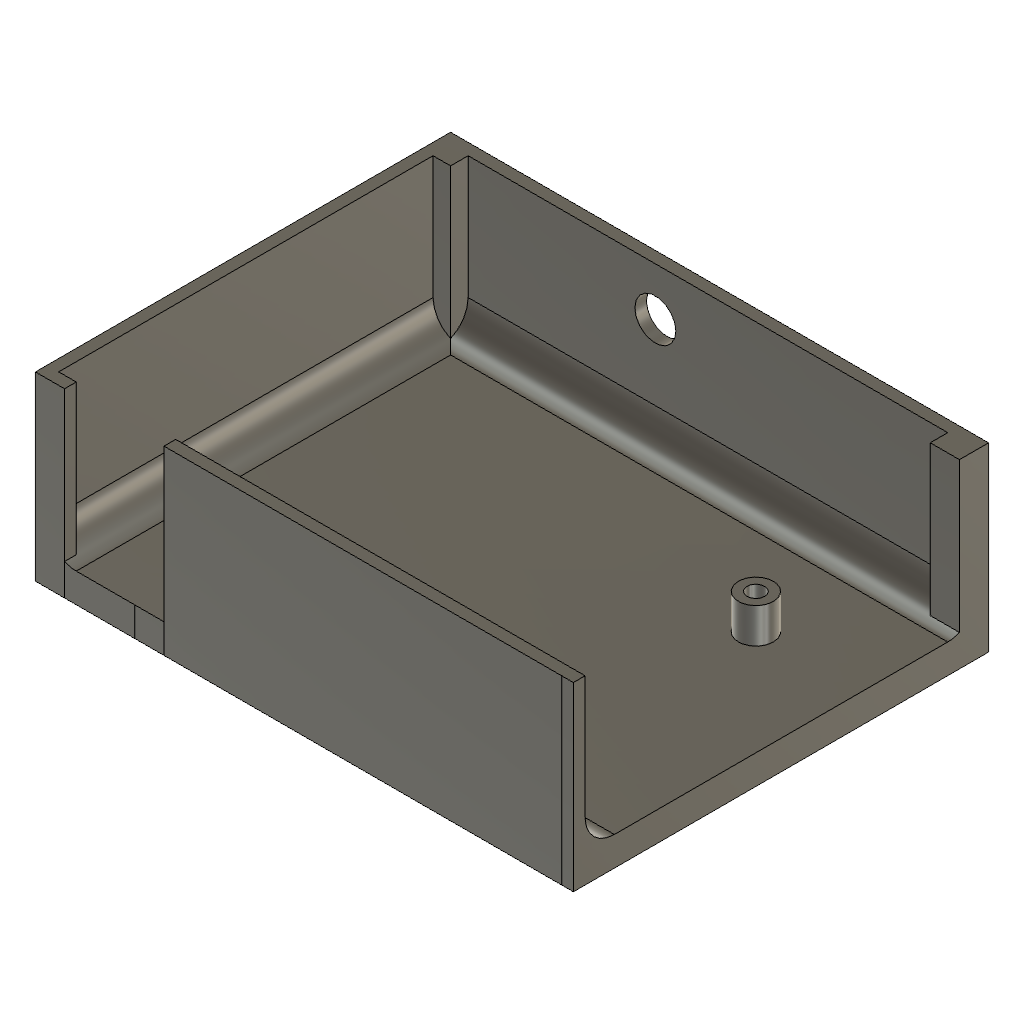
HAB2 Recovery Circuit Case (Autodesk Fusion 360 design; units mm, degrees)
part number: 2026-10-17-16-52-14-798
Autodesk Fusion 360 part; units mm, degrees
sketch "Sketch1" plane through (0, 0, 0) normal (0, 0, 1) x (1, 0, 0)
  line L0 (30, 20) -> (-30, 20)
  line L1 (-30, 20) -> (-30, -20)
  line L2 (-30, -20) -> (30, -20)
  line L3 (30, -20) -> (30, 20)
  line L4 (30, 20) -> (-30, -20) construction
  line L5 (-30, 20) -> (30, -20) construction
  line L6 (-30, -20) -> (-27.5, -20)
  line L7 (-27.5, -20) -> (-27.5, -17.5)
  line L8 (-27.5, -17.5) -> (-30, -17.5)
  line L9 (-30, -17.5) -> (-30, -20)
  line L10 (30, 20) -> (27.1, 20)
  line L11 (27.1, 20) -> (27.1, 17.1)
  line L12 (27.1, 17.1) -> (30, 17.1)
  line L13 (30, 17.1) -> (30, 20)
  circle A0 centre (-27.5, -17.5) radius 1.5
  circle A1 centre (27.1, 17.1) radius 1.5
  line L14 (-30, -20) -> (30, -20)
  line L15 (30, -20) -> (30, -30)
  line L16 (30, -30) -> (-30, -30)
  line L17 (-30, -30) -> (-30, -20)
  line L18 (-30, 20) -> (-45, 20)
  line L19 (-45, 20) -> (-45, -30)
  line L20 (-45, -30) -> (-30, -30)
  line L21 (-30, -30) -> (-30, 20)
  line L22 (30, 20) -> (-45, 20)
  line L23 (-45, 20) -> (-45, 37)
  line L24 (-45, 37) -> (30, 37)
  line L25 (30, 37) -> (30, 20)
  line L26 (30, 37) -> (43, 37)
  line L27 (43, 37) -> (43, -30)
  line L28 (43, -30) -> (30, -30)
  line L29 (30, -30) -> (30, 37)
  line L30 (-45, 37) -> (-47, 37)
  line L31 (-47, 37) -> (-47, 39)
  line L32 (-47, 39) -> (-45, 39)
  line L33 (-45, 39) -> (-45, 37)
  line L34 (-45, -30) -> (-47, -30)
  line L35 (-47, -30) -> (-47, -32)
  line L36 (-47, -32) -> (-45, -32)
  line L37 (-45, -32) -> (-45, -30)
  line L38 (43, -30) -> (45, -30)
  line L39 (45, -30) -> (45, -32)
  line L40 (45, -32) -> (43, -32)
  line L41 (43, -32) -> (43, -30)
  line L42 (43, 37) -> (45, 37)
  line L43 (45, 37) -> (45, 39)
  line L44 (45, 39) -> (43, 39)
  line L45 (43, 39) -> (43, 37)
  line L46 (-47, 37) -> (-47, -30)
  line L47 (-45, -32) -> (43, -32)
  line L48 (45, -30) -> (45, 37)
  line L49 (43, 39) -> (-45, 39)
  circle A2 centre (-27.5, -17.5) radius 3
  circle A3 centre (27.1, 17.1) radius 3
  line L50 (-47, -32) -> (-42, -32)
  line L51 (-42, -32) -> (-42, -27)
  line L52 (-42, -27) -> (-47, -27)
  line L53 (-47, -27) -> (-47, -32)
  line L54 (-47, -32) -> (-42, -27)
  line L55 (-42, -32) -> (-47, -27)
  line L56 (45, 39) -> (40, 39)
  line L57 (40, 39) -> (40, 34)
  line L58 (40, 34) -> (45, 34)
  line L59 (45, 34) -> (45, 39)
  line L60 (45, 39) -> (40, 34)
  line L61 (45, 34) -> (40, 39)
  line L62 (-47, 39) -> (-42, 39)
  line L63 (-42, 39) -> (-42, 34)
  line L64 (-42, 34) -> (-47, 34)
  line L65 (-47, 34) -> (-47, 39)
  line L66 (-47, 39) -> (-42, 34)
  line L67 (-47, 34) -> (-42, 39)
  line L68 (-30, -30) -> (-30, -32)
  line L69 (-30, -30) -> (-25, -30)
  line L70 (-25, -30) -> (-25, -32)
  line L71 (-25, -32) -> (-30, -32)
  line L72 (-30, -32) -> (-30, -30)
  line L73 (27.1, 17.1) -> (28.1, 17.1)
  line L74 (28.1, 17.1) -> (28.1, 18.1)
  line L75 (28.1, 18.1) -> (27.1, 18.1)
  line L76 (27.1, 18.1) -> (27.1, 17.1)
  dimension "d1" = 60
  dimension "d2" = 40
  dimension "d6" = 2.5
  dimension "d7" = 2.5
  dimension "d8" = 2.9
  dimension "d9" = 2.9
  dimension "d12" = 3
  dimension "d13" = 3
  dimension "d15" = 10
  dimension "d16" = 15
  dimension "d17" = 17
  dimension "d18" = 13
  dimension "d19" = 2
  dimension "d20" = 2
  dimension "d21" = 2
  dimension "d22" = 2
  dimension "d23" = 2
  dimension "d24" = 2
  dimension "d25" = 2
  dimension "d26" = 2
  dimension "d31" = 6
  dimension "d32" = 6
  dimension "d43" = 5
  dimension "d44" = 5
  dimension "d45" = 5
  dimension "d46" = 5
  dimension "d47" = 5
  dimension "d48" = 5
  dimension "d49" = 5
  dimension "d65" = 1
  dimension "d66" = 1
  constraint horizontal L0
  constraint perpendicular L0 L1
  constraint parallel L0 L2
  constraint parallel L1 L3
  constraint coincident L4 origin
  constraint coincident L5 origin
  constraint horizontal L6
  constraint vertical L7
  constraint horizontal L8
  constraint vertical L9
  constraint horizontal L10
  constraint vertical L11
  constraint horizontal L12
  constraint vertical L13
  constraint coincident L7.end L8.start
  constraint coincident L11.end L12.start
  constraint horizontal L14
  constraint vertical L15
  constraint horizontal L16
  constraint vertical L17
  constraint horizontal L18
  constraint vertical L19
  constraint horizontal L20
  constraint vertical L21
  constraint horizontal L22
  constraint vertical L23
  constraint horizontal L24
  constraint vertical L25
  constraint horizontal L26
  constraint vertical L27
  constraint horizontal L28
  constraint vertical L29
  constraint horizontal L30
  constraint vertical L31
  constraint horizontal L32
  constraint vertical L33
  constraint horizontal L34
  constraint vertical L35
  constraint horizontal L36
  constraint vertical L37
  constraint horizontal L38
  constraint vertical L39
  constraint horizontal L40
  constraint vertical L41
  constraint horizontal L42
  constraint vertical L43
  constraint horizontal L44
  constraint vertical L45
  constraint concentric A0 A2
  constraint concentric A1 A3
  constraint horizontal L50
  constraint vertical L51
  constraint horizontal L52
  constraint vertical L53
  constraint horizontal L56
  constraint vertical L57
  constraint horizontal L58
  constraint vertical L59
  constraint horizontal L62
  constraint vertical L63
  constraint horizontal L64
  constraint vertical L65
  constraint coincident L47 L68.end
  constraint perpendicular L47 L68
  constraint horizontal L69
  constraint vertical L70
  constraint horizontal L71
  constraint vertical L72
  constraint horizontal L73
  constraint vertical L74
  constraint horizontal L75
  constraint vertical L76
  measures "d1" distance of L1.end L2.end
  measures "d2" distance of L0.end L1.end
  measures "d6" distance of L1.end L6.end
  measures "d7" distance of L1.end L8.end
  measures "d8" distance of L0.start L10.end
  measures "d9" distance of L0.start L12.end
  measures "d12" diameter of A0
  measures "d13" diameter of A1
  measures "d15" distance of L1.end L16.end
  measures "d16" distance of L0.end L18.end
  measures "d17" distance of L0.start L24.end
  measures "d18" distance of L24.end L26.end
  measures "d19" distance of L23.end L30.end
  measures "d20" distance of L23.end L32.end
  measures "d21" distance of L19.end L34.end
  measures "d22" distance of L19.end L36.end
  measures "d23" distance of L27.end L38.end
  measures "d24" distance of L27.end L40.end
  measures "d25" distance of L26.end L42.end
  measures "d26" distance of L26.end L44.end
  measures "d31" diameter of A2
  measures "d32" diameter of A3
  measures "d43" distance of L35.end L50.end
  measures "d44" distance of L35.end L52.end
  measures "d45" distance of L43.end L56.end
  measures "d46" distance of L43.end L58.end
  measures "d47" distance of L31.end L62.end
  measures "d48" distance of L31.end L64.end
  measures "d49" distance of L16.end L69.end
  measures "d65" distance of L11.end L73.end
  measures "d66" distance of L11.end L75.end
extrude "Extrude1" add sketch "Sketch1" against normal blind 5 contours L0 L3 L10 L13 L22 L29 A3 | L3 L13 L15 L25 L26 L27 L28 L29 A3 L57 L58 | L0 L10 L18 L22 L23 L24 L25 L29 A3 L63 L64 | L0 L3 L10 L11 L12 L13 A1 L22 L29 A3 | L0 L10 L22 A3 | L3 L13 L29 A3 | L24 L26 L49 L57 L63 | L0 L3 L11 L12 A1 L22 L29 A3 | L0 L1 L2 L3 L14 L21 L22 L29 A2 A3 | L24 L63 L66 L67 | L24 L63 L67 | L26 L57 L61 | L26 L57 L60 L61 | L1 L9 L17 L18 L19 L20 L21 L22 A2 L51 L52 | L24 L66 L67 | L24 L33 L49 L62 L67 | L23 L64 L66 L67 | L26 L45 L49 L56 L61 | L26 L60 L61 | L27 L58 L60 L61 | L1 L2 L7 L8 A0 L14 L21 A2 | L1 L9 L21 A2 | L19 L23 L46 L52 L64 | L2 L6 L14 L15 L16 L17 L21 L29 A2 L69 | L23 L66 L67 | L23 L30 L46 L65 L67 | L32 L33 L62 L66 | L30 L31 L65 L66 | L23 L64 L67 | L27 L42 L48 L59 L61 | L42 L43 L59 L60 | L44 L45 L56 L60 | L27 L60 L61 | L27 L38 L48 L58 | L27 L58 L61 | L1 L2 L6 L7 L8 L9 A0 L14 L21 A2 | L1 L2 L6 L9 L14 L21 A2 | L19 L52 L54 L55 | L19 L52 L55 | L2 L6 L14 A2 | L16 L28 L41 L47 L70 | L38 L39 L40 L41 | L19 L54 L55 | L19 L34 L46 L53 L55 | L20 L51 L54 L55 | L16 L47 L68 L69 L70 L71 L72 | L20 L47 L51 L68 L72 | L20 L54 L55 | L34 L35 L53 L54 | L20 L37 L47 L50 L55 | L36 L37 L50 L54 | L20 L51 L55
extrude "Extrude2" add sketch "Sketch1" along normal blind 6 contours L0 L3 L10 L11 L12 L13 A1 L22 L29 A3 | L0 L10 L22 A3 | L3 L13 L29 A3 | L0 L3 L11 L12 A1 L22 L29 A3 | L1 L2 L7 L8 A0 L14 L21 A2 | L1 L9 L21 A2 | L1 L2 L6 L7 L8 L9 A0 L14 L21 A2 | L2 L6 L14 A2
extrude "Extrude4" add sketch "Sketch1" along normal blind 26 contours L24 L26 L49 L57 L63 | L24 L63 L66 L67 | L24 L63 L67 | L26 L57 L61 | L26 L57 L60 L61 | L24 L66 L67 | L24 L33 L49 L62 L67 | L23 L64 L66 L67 | L26 L45 L49 L56 L61 | L26 L60 L61 | L27 L58 L60 L61 | L19 L23 L46 L52 L64 | L23 L66 L67 | L23 L30 L46 L65 L67 | L32 L33 L62 L66 | L30 L31 L65 L66 | L23 L64 L67 | L27 L42 L48 L59 L61 | L42 L43 L59 L60 | L44 L45 L56 L60 | L27 L60 L61 | L27 L58 L61 | L19 L52 L55 | L16 L28 L41 L47 L70 | L38 L39 L40 L41 | L19 L34 L46 L53 L55 | L34 L35 L53 L54 | L20 L37 L47 L50 L55 | L36 L37 L50 L54 | L20 L51 L55
fillet "Fillet1" radius 5 3 edges at (-1, 37, 0) (-45, 2, 0) (10, -30, 0)
sketch "Sketch4" plane through (0, 37, 0) normal (0, -1, 0) x (1, 0, 0)
  line L0 (-42, 5) -> (40, 5)
  line L1 (40, 5) -> (40, 26)
  line L2 (40, 26) -> (-42, 26)
  line L3 (-42, 26) -> (-42, 5)
  line L4 (-30, 10.75) -> (-10, 10.75)
  line L5 (-10, 10.75) -> (-10, 17.75)
  line L6 (-10, 17.75) -> (-30, 17.75)
  line L7 (-30, 17.75) -> (-30, 10.75)
  circle A0 centre (-10, 17.75) radius 3.5
  point P0 (-30, 10.75)
  dimension "d52" = 20
  dimension "d53" = 7
  dimension "d54" = 7
  constraint horizontal L4
  constraint vertical L5
  constraint horizontal L6
  constraint vertical L7
  constraint coincident P0 L4.start
  constraint coincident L5.end L6.start
  measures "d52" distance of P0 L4.end
  measures "d53" distance of P0 L6.end
  measures "d54" diameter of A0
extrude "Extrude6" cut sketch "Sketch4" against normal blind 2 contours L5 L6 A0 | L5 L6 A0
sketch "Sketch8" plane through (0, 0, -5) normal (0, 0, -1) x (1, 0, 0)
  circle A0 centre (27.1, -17.1) radius 1.5
  circle A1 centre (-27.5, 17.5) radius 1.5
  line L0 (45, -39) -> (45, 32)
  line L1 (45, 32) -> (43, 32)
  line L2 (43, 32) -> (-25, 32)
  line L3 (-25, 32) -> (-30, 32)
  line L4 (-30, 32) -> (-42, 32)
  line L5 (-42, 32) -> (-47, 32)
  line L6 (-47, 32) -> (-47, 27)
  line L7 (-47, 27) -> (-47, -34)
  line L8 (-47, -34) -> (-47, -39)
  line L9 (-47, -39) -> (45, -39)
  circle A2 centre (27.1, -17.1) radius 2.25
  circle A3 centre (-27.5, 17.5) radius 2.25
  dimension "d67" = 4.5
  dimension "d68" = 4.5
  constraint concentric A0 A2
  constraint concentric A1 A3
  measures "d67" diameter of A2
  measures "d68" diameter of A3
extrude "Extrude8" cut sketch "Sketch8" against normal blind 3 contours A2 | A3
